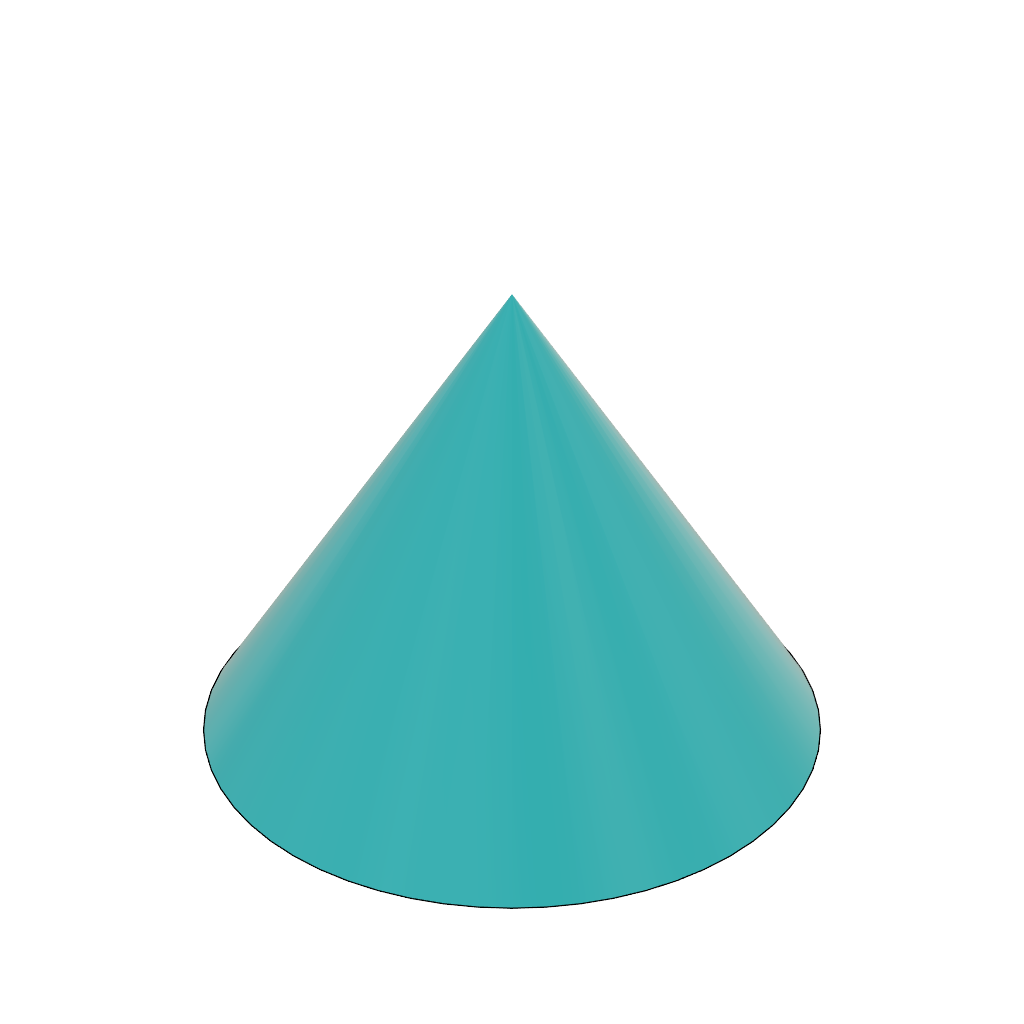
level -1 cone (Autodesk Fusion 360 design; units mm, degrees)
part number: 2026-10-11-11-30-56-584
Autodesk Fusion 360 part; units mm, degrees
sketch "Sketch3" plane through (0, 0, 0) normal (0, 1, 0) x (1, 0, 0)
  circle A0 centre (0, 0) radius 37.5
  dimension "d4" = 75
  constraint coincident A0.centre origin
  measures "d4" diameter of A0
extrude "Extrude2" add sketch "Sketch3" along normal blind 65 draft -30
